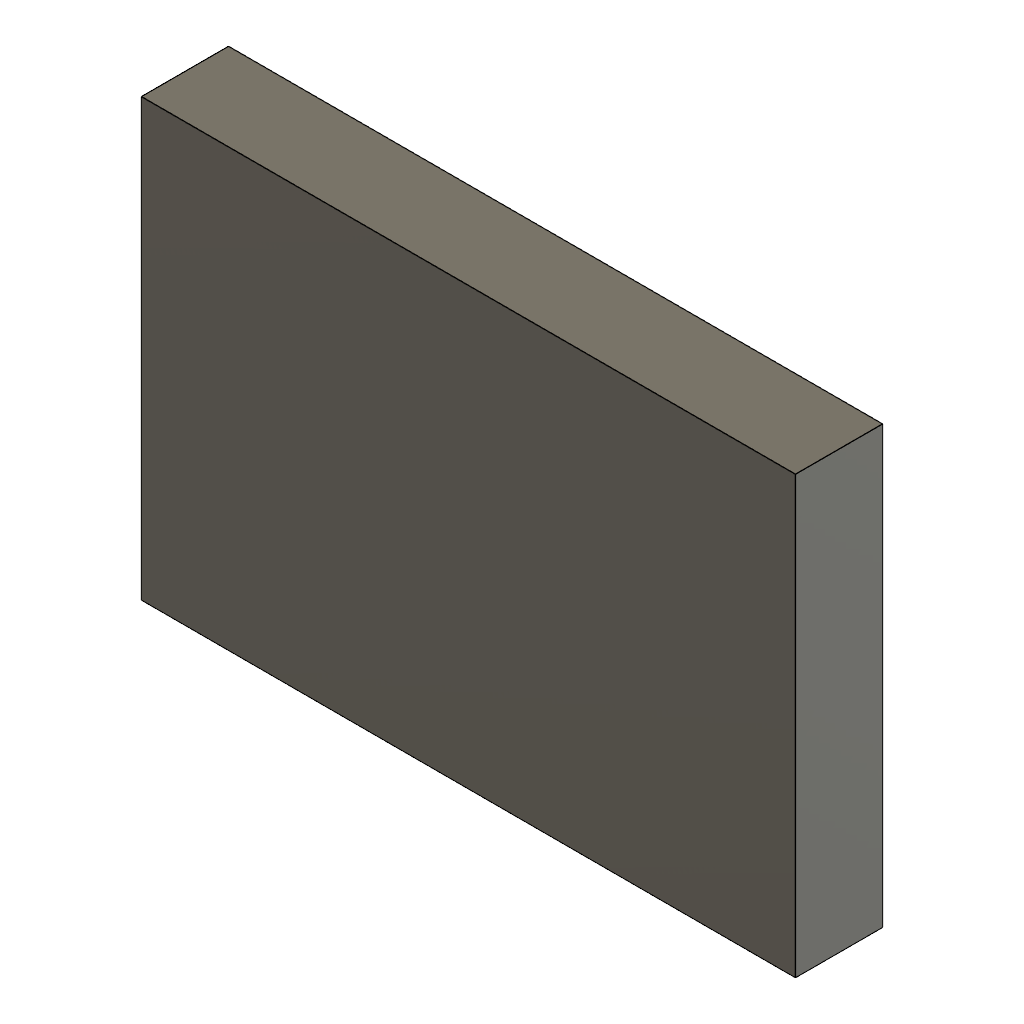
sk_construction_lines_mixed (Autodesk Fusion 360 design; units mm, degrees)
part number: 2026-11-13-14-35-25-672
Autodesk Fusion 360 part; units mm, degrees
sketch "Sketch1" plane through (0, 0, 0) normal (0, 0, 1) x (1, 0, 0)
  line L0 (0, 0) -> (30, 0)
  line L1 (30, 0) -> (30, 20)
  line L2 (30, 20) -> (0, 20)
  line L3 (0, 20) -> (0, 0)
  line L4 (0, 0) -> (30, 20) construction
  circle A0 centre (15, 10) radius 5 construction
  line L5 (15, 0) -> (15, 20) construction
extrude "Extrude1" add sketch "Sketch1" along normal blind 4
